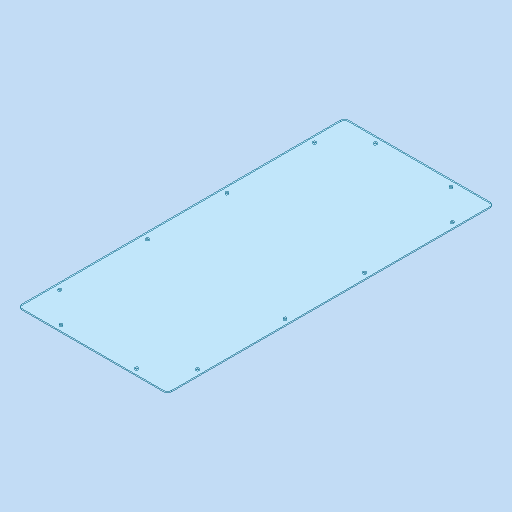
# Autodesk Inventor part: MM0948AN170_G01_110
Saved by Autodesk Inventor 2023.3 (Build 273359000, 359)
## iProperties
Part Number: MM0948AN170_G01_110
Material: Kst - PC (Eslon, klar)
Description: =<RBPARTNOTITLE2>
Document SubType Name: Modeling
Designer: Benutzer
Mass: 1107.98 g
Surface Area: 6234.61 cm^2
Volume: 923.317 cm^3
Density: 1.2 g/cm^3
Appearance: Klar AnP
Created: 2023-03-23
RBDOCUMENTTYPE: DRF
RBDOCUMENTVERSION: 00
RBDRAWINGMAINSCALE: 1:1
RBDRAWINGMISSINGSPEC: --
RBDRAWINGVOLUME: --
RBGBEDGESIN1: +0,5
RBGBEDGESIN2: +0,2
RBGBEDGESOUT1: -0,3
RBGBEDGESOUT2: -0,1
RBMATERIAL: =<Material>
RBMATMEETS: --
RBMATNO: =<Part Number>
RBPARTMADEOF: 3 x 820 x 376 (FM)
RBPARTNO: SIEHE MNR
RBPARTNOTITLE1: manufactured part
RBPARTNOTITLE2: Anfertigungsteil
RBPARTSAFETYINDICATOR: --
RBSURFACE: --
RBSURFACE2: --
RBZEDGESNORM: ISO13715:2002-06
RBZGENDIMCLASS: m
RBZGENDIMNORM: ISO 2768-1:1989-11
RBZGENGEOCLASS: H
RBZGENGEONORM: ISO 2768-2:1989-11
RBZSURFACENORM: ISO13D2:2002-02
RBZTOLERANCENORM: ISO 14405-1:2010-12
AnP_Material: =<Material>
AnP_TemplVers: 20190222
AnP_Kategorie: 1
MaxAbmaße: 3 x 820 x 376 (FM)
AnP_Kommentar_aktuell: =<Comments>
AnP_Material_aktuell: =<Material>
Author: FH/Wi
Keywords: =<RBPARTMADEOF>
Comments: =<RBSURFACE2>
Revision Number: 01
Autodesk Inventor part; units mm, degrees
ref_plane "YZ Plane" through (0, 0, 0) normal (1, 0, 0) x (0, 1, 0)
ref_plane "XZ Plane" through (0, 0, 0) normal (0, 1, 0) x (-1, 0, 0)
ref_plane "XY Plane" through (0, 0, 0) normal (0, 0, 1) x (1, 0, 0)
sketch "Skizze1" plane through (0, 0, 0) normal (0, 0, 1) x (1, 0, 0)
  line L0 (0, 0) -> (376, 0)
  line L1 (376, 0) -> (376, 820)
  line L2 (376, 820) -> (0, 820)
  line L3 (0, 820) -> (0, 0)
  dimension "d0" = 376
  dimension "d1" = 820
  constraints: 8 end point, 2 parallel, 1 horizontal, 1 perpendicular
  measures "d0" distance of L2.end L1.end
  measures "d1" distance of L1.end L0.end
extrude "Extrusion1" add sketch "Skizze1" along normal blind 3
fillet "Rundung1" radius 10 4 edges at (376, 0, 1.5) (0, 0, 1.5) (0, 820, 1.5) (376, 820, 1.5)
sketch "Skizze2" plane through (0, 0, 3) normal (0, 0, 1) x (1, 0, 0)
  line L0 (366, 820) -> (10, 820) projected
  line L1 (0, 810) -> (0, 10) projected
  line L2 (376, 10) -> (376, 810) projected
  line L3 (10, 0) -> (366, 0) projected
  point P0 (0, 0)
  point P1 (93, 805)
  point P2 (283, 805)
  point P3 (361, 730)
  point P4 (361, 510)
  point P5 (361, 310)
  point P6 (361, 90)
  point P7 (283, 15)
  point P8 (93, 15)
  point P9 (15, 90)
  point P10 (15, 310)
  point P11 (15, 510)
  point P12 (15, 730)
  dimension "d5" = 15
  dimension "d6" = 15
  dimension "d7" = 15
  dimension "d8" = 15
  dimension "d9" = 190
  dimension "d12" = 376
  dimension "d14" = 220
  dimension "d15" = 200
  dimension "d16" = 220
  dimension "d17" = 820
  dimension "d18" = 90
  dimension "d34" = 93
  dimension "d35" = 346
  constraints: 8 vertical alignment, 6 horizontal alignment
  measures "d5" distance from line of point (93, 805) L0
  measures "d6" distance from line of point (15, 730) L1
  measures "d7" distance from line of point (361, 730) L2
  measures "d8" distance from line of L3 point (93, 15)
  measures "d9" distance of point (283, 15) point (93, 15)
  measures "d12" distance between parallel lines of L2 L1
  measures "d14" distance of point (15, 310) point (15, 90)
  measures "d15" distance of point (15, 510) point (15, 310)
  measures "d16" distance of point (15, 730) point (15, 510)
  measures "d17" distance between parallel lines of L3 L0
  measures "d18" distance from line of point (15, 730) L0
  measures "d34" distance from line of L1 point (93, 15)
  measures "d35" distance of point (361, 90) point (15, 90)
hole "Bohrung1" at (93, 805, 3) at (283, 805, 3) at (361, 730, 3) at (361, 510, 3) at (361, 310, 3) at (361, 90, 3) at (283, 15, 3) at (93, 15, 3) at (15, 90, 3) at (15, 310, 3) at (15, 510, 3) at (15, 730, 3) direction (0, 0, -1) diameter 7 end through all
equation "\"d34\" = -0.5 * d9 + 0.5 * d12"
